Autodesk Fusion 360 part; units mm, degrees
(part 2 of 2)
equation "n_base_bolt = n_base_bolt_Ref" comment "LINKED: n_base_bolt_Ref, derived from 100000_P04_POD-SKELETON_CAD v4 (skeleton is the single source)"
equation "tube_w = 20 mm" comment "CONFIRMED: D-34, D-54: aluminium tube 20 x 40 x 1.2; the 20 mm face carries the skin, so the 40 mm runs through the wall (outer_t = ACP 3 + frame 40). The joint register may turn it for the bond width (HOLD)"
equation "tube_d = outer_t - skin_t - bond_t" comment "CALCULATION: frame depth = outer panel 46 - skin 3 - bond 3 = 40 (D-34)"
equation "tube_t = 1.2 mm" comment "CONFIRMED: D-34, D-54, D-85: perimeter members (rails, front and back stiles) keep the 1.2 mm wall; they carry the rivnuts (grip check passed)"
equation "stud_t = 1.0 mm" comment "CONFIRMED: D-85 (weight): intermediate studs at a 1.0 mm wall; they carry no rivnut, only the skin's bond line"
equation "stile_pitch_max = 400 mm" comment "CONFIRMED: D-16, D-34: members 400 mm apart or less, to keep the ACP flat"
equation "skin_setback = 0 mm" comment "ASSUMPTION: skin edge set back from the frame's top and bottom edges: 0, so the outside reveal equals the 2.26 seam gap (D-23: crisp, aligned reveals; joints register 2.8 leaves the setback to the WALL drawing)"
equation "fill_t = tube_d" comment "CALCULATION: 40 mm PET fill fills the frame depth (D-34; layout study 40 mm)"
equation "bolt_d = 7 mm" comment "CONFIRMED: PM ruling on F-009: bolt holes 7.0 (0.51 float), position tolerance 0.4 (+-0.2) from the spigot hole, CNC or drill jig (joints register FR-02)"
equation "access_d = 19 mm" comment "CALCULATION: register FR-03: passes the 18 mm head washer (ISO 7093-1, R-J10), the M6 head and the 5 mm key; holds the grommet retainer (H-02)"
equation "bolt_line_y = pod_d / 2 - skin_t - bond_t - tube_d / 2" comment "CONFIRMED: J-WALL-02 bolt line on the back panel's tube centre, Y 824 (joints register R-J15, FR-07)"
equation "rivnut_d = 9.53 mm" comment "SOURCE: Sherex CAH3-610-4.2 hole 9.53 +0.10 (HW-SEL A5; register H-03)"
equation "spigot_d = 8.5 mm" comment "ASSUMPTION: register FR-05: hole for the 8 mm locating spigot H-05"
equation "spigot_slot = 14 mm" comment "ASSUMPTION: register FR-05: slot length for the second spigot"
equation "spigot_edge = spigot_inset" comment "CALCULATION: the skeleton's spigot_inset: spigots 100 from each end of the edge (PM ruling 2026-10-31, R-J13)"
equation "bolt_edge = bolt_edge_inset" comment "CALCULATION: the skeleton's bolt_edge_inset: end bolts 220 in from the panel's ends, evenly spaced, every bolt 30 or more from any stile (PM ruling 2026-10-31, R-J14)"
equation "pocket_w = 60 mm" comment "ASSUMPTION: register FR-10: fill left out 60 x 60 next to each bolt for the key"
equation "felt_t = 9 mm" comment "SOURCE: plan VT03-PET 9 mm PET felt; HW-SEL A3; D-31 (the factory's felt)"
equation "tray_t = 0.5 mm" comment "CONFIRMED: D-37: galvanised steel tray 0.5 mm"
equation "tray_h = cass_t" comment "CONFIRMED: PM ruling 2026-10-31 (WALL group, option 1): the wall cassettes use the ceiling's tray, returns the full cassette depth (34) turned in as lips that hold the felt, no ribs; settles H09 for the walls"
equation "lip_w = 12 mm" comment "CONFIRMED: PM ruling 2026-10-31 (WALL group, option 1): 12 mm lips hold the felt edge"
equation "bend_r = tray_t" comment "ASSUMPTION: inside bend radius 1 x t for 0.5 mm DX51D (the sheet metal rule's bend radius is its Thickness); the factory's tooling sets it (guideline 9)"
equation "felt_c = 1 mm" comment "ASSUMPTION: felt edge clearance inside the returns, as the ceiling cassette"
equation "gap_h = tray_h - felt_t - 2 * tray_t" comment "CALCULATION: air gap between the tray base and the felt (24): the acoustic gap (D-17) and the cable path (D-26)"
equation "clip_zone_h = 60 mm" comment "ASSUMPTION: height of each reserved clip zone (H03: no clip named)"
equation "clip_zone_dz = 100 mm" comment "ASSUMPTION: clip zone centre from the cassette's top and bottom edges (H03)"
equation "stopw_od = 20 mm" comment "SOURCE: joints register H-08: stop washer Ø10.5 x Ø20 x 1.5 (PROPOSED part)"
equation "stopw_id = 10.5 mm" comment "SOURCE: joints register H-08"
equation "stopw_t = 1.5 mm" comment "SOURCE: joints register H-08: rivnut head 0.76 + washer 1.5 = the 2.26 stop (R-J5)"
equation "rivnut_head_d = 12.96 mm" comment "SOURCE: Sherex CAH3-610-4.2 head Ø12.96 (joints register H-03, SHX)"
equation "rivnut_head_t = 0.76 mm" comment "SOURCE: Sherex CAH3-610-4.2 head 0.76 ±0.08 (H-03, SHX)"
equation "rivnut_body_d = 9.5 mm" comment "SOURCE: Sherex CAH3-610-4.2 body Ø9.50 max (H-03, SHX)"
equation "rivnut_len = 10.16 mm" comment "SOURCE: Sherex CAH3-610-4.2 installed length 10.16 max under the head (H-03, SHX); the bulge inside the tube is not modelled"
equation "m6_d = 6 mm" comment "CALCULATION: M6 threads shown at their 6 mm major diameter (no modelled thread)"
equation "spigot_pin_d = 8 mm" comment "SOURCE: joints register H-05: Ø8 stainless pin (PROPOSED, assumption sizes)"
equation "spigot_proud = 8 mm" comment "SOURCE: joints register H-05: stands 8 proud (read as: of the joint face)"
equation "spigot_thread_l = 10 mm" comment "ASSUMPTION: M6 thread into the spigot rivnut; H-05 gives no length; 10 stays inside the rivnut's 10.16"
equation "lead_in = 1 mm" comment "SOURCE: joints register 2.10 (R-J9): 1 x 45 degree lead-in on the top edge of each closing-seam face, so the panel beside it drops in past it without catching the bulb seal"
equation "pnl_len = half_pw" comment "CALCULATION: skeleton half_pw: the back panel's skin width (1200.61 on P04)"
equation "frm_len = half_fw" comment "CALCULATION: the skeleton's half_fw, 1198.99: the frame stops close_gap / 2 from X 0 and 1.62 short of its skin (R-J16)"
equation "pnl_h = back_ph" comment "CALCULATION: skeleton back row height (1118.61 on P04)"
equation "frm_h = pnl_h" comment "CALCULATION: the frame fills the row height; the seam gaps are outside it (P04)"
equation "top_h = tube_w" comment "CALCULATION: the back panels' top rails stay 20 x 40 (the ceiling's back member is the 40 x 40, R-J3)"
equation "stile_n_mid = ceil(( frm_len - tube_w ) / stile_pitch_max) - 1" comment "CALCULATION: intermediate stiles so that no stile pitch exceeds stile_pitch_max"
equation "stile_pitch = ( frm_len - tube_w ) / ( stile_n_mid + 1 )" comment "CALCULATION: equal stile pitch, centre to centre"
equation "stile_len = frm_h - 2 * tube_w" comment "CALCULATION: stiles between the full-width rails (butt joints)"
equation "n_len_bolt = n_base_bolt" comment "CALCULATION: the skeleton's n_base_bolt (4): also on the horizontal seam and the ceiling back edge (register 2.9; the skeleton's n_ceil_back_bolt 3 is an old assumption, flagged)"
equation "len_bolt_pitch = ( frm_len - 2 * bolt_edge ) / ( n_len_bolt - 1 )" comment "CALCULATION: 253.00 on P04: 220, 473.00, 725.99, 978.99 from the frame's ends (register 2.9; the skeleton's back_base_pitch uses the 1200.61 skin and gives 253.54, flagged to its owner)"
equation "n_side_jnt = 3" comment "SOURCE: 3 bolts on the back corner and on the closing seam (register 2.9)"
equation "side_jnt_pitch = ( pnl_h - 2 * bolt_edge ) / ( n_side_jnt - 1 )" comment "CALCULATION: 339.31 on P04: 220, 559.31, 898.61 up the 1118.61 edge (register 2.9)"
equation "cass_len = pod_w / 2 - stack_t - seam_gap / 2" comment "ASSUMPTION: PROPOSED (WALL): from the side lining's face to seam_gap / 2 short of X 0. Each cassette hangs on its own panel's frame and the closing seam moves (5.2 to 5.8, register 2.11), so the skeleton's touching edges at X 0 could clash; a 2.26 gap matches the skin seam above it (R-J16) and takes the H-14 edge seal"
equation "cass_h = pnl_h" comment "CALCULATION: lower: the row height; upper: up to lin_gap under the ceiling frame, floating (D-57; P04)"
equation "d677 = panel_z0"
equation "d679 = ( -close_gap / 2 ) - ( -close_gap / 2 - half_fw )"
equation "d680 = ( pod_d / 2 - skin_t - bond_t ) - ( pod_d / 2 - outer_t )"
equation "d681 = abs(-close_gap / 2 - half_fw)"
equation "d682 = abs(pod_d / 2 - outer_t)"
equation "d683 = ( ( panel_z0 ) + tube_w ) - ( panel_z0 )"
equation "d685 = ( panel_z0 ) + tube_t"
equation "d687 = ( -close_gap / 2 ) - ( -close_gap / 2 - half_fw )"
equation "d688 = ( ( pod_d / 2 - skin_t - bond_t ) - tube_t ) - ( ( pod_d / 2 - outer_t ) + tube_t )"
equation "d689 = abs(-close_gap / 2 - half_fw)"
equation "d690 = abs(( pod_d / 2 - outer_t ) + tube_t)"
equation "d691 = ( ( ( panel_z0 ) + tube_w ) - tube_t ) - ( ( panel_z0 ) + tube_t )"
equation "d693 = ( panel_z0 + back_ph ) - top_h"
equation "d695 = ( -close_gap / 2 ) - ( -close_gap / 2 - half_fw )"
equation "d696 = ( pod_d / 2 - skin_t - bond_t ) - ( pod_d / 2 - outer_t )"
equation "d697 = abs(-close_gap / 2 - half_fw)"
equation "d698 = abs(pod_d / 2 - outer_t)"
equation "d699 = ( panel_z0 + back_ph ) - ( ( panel_z0 + back_ph ) - top_h )"
equation "d701 = ( ( panel_z0 + back_ph ) - top_h ) + tube_t"
equation "d703 = ( -close_gap / 2 ) - ( -close_gap / 2 - half_fw )"
equation "d704 = ( ( pod_d / 2 - skin_t - bond_t ) - tube_t ) - ( ( pod_d / 2 - outer_t ) + tube_t )"
equation "d705 = abs(-close_gap / 2 - half_fw)"
equation "d706 = abs(( pod_d / 2 - outer_t ) + tube_t)"
equation "d707 = ( ( panel_z0 + back_ph ) - tube_t ) - ( ( ( panel_z0 + back_ph ) - top_h ) + tube_t )"
equation "d709 = ( panel_z0 ) + tube_w"
equation "d711 = ( ( -close_gap / 2 - half_fw ) + tube_w ) - ( -close_gap / 2 - half_fw )"
equation "d712 = ( pod_d / 2 - skin_t - bond_t ) - ( pod_d / 2 - outer_t )"
equation "d713 = abs(-close_gap / 2 - half_fw)"
equation "d714 = abs(pod_d / 2 - outer_t)"
equation "d715 = ( ( panel_z0 + back_ph ) - top_h ) - ( ( panel_z0 ) + tube_w )"
equation "d717 = ( panel_z0 ) + tube_w"
equation "d719 = ( ( ( -close_gap / 2 - half_fw ) + tube_w ) - tube_t ) - ( ( -close_gap / 2 - half_fw ) + tube_t )"
equation "d720 = ( ( pod_d / 2 - skin_t - bond_t ) - tube_t ) - ( ( pod_d / 2 - outer_t ) + tube_t )"
equation "d721 = abs(( -close_gap / 2 - half_fw ) + tube_t)"
equation "d722 = abs(( pod_d / 2 - outer_t ) + tube_t)"
equation "d723 = ( ( panel_z0 + back_ph ) - top_h ) - ( ( panel_z0 ) + tube_w )"
equation "d725 = ( panel_z0 ) + tube_w"
equation "d727 = ( -close_gap / 2 ) - ( ( -close_gap / 2 ) - tube_w )"
equation "d728 = ( pod_d / 2 - skin_t - bond_t ) - ( pod_d / 2 - outer_t )"
equation "d729 = abs(( -close_gap / 2 ) - tube_w)"
equation "d730 = abs(pod_d / 2 - outer_t)"
equation "d731 = ( ( panel_z0 + back_ph ) - top_h ) - ( ( panel_z0 ) + tube_w )"
equation "d733 = ( panel_z0 ) + tube_w"
equation "d735 = ( ( -close_gap / 2 ) - tube_t ) - ( ( ( -close_gap / 2 ) - tube_w ) + tube_t )"
equation "d736 = ( ( pod_d / 2 - skin_t - bond_t ) - tube_t ) - ( ( pod_d / 2 - outer_t ) + tube_t )"
equation "d737 = abs(( ( -close_gap / 2 ) - tube_w ) + tube_t)"
equation "d738 = abs(( pod_d / 2 - outer_t ) + tube_t)"
equation "d739 = ( ( panel_z0 + back_ph ) - top_h ) - ( ( panel_z0 ) + tube_w )"
equation "d741 = ( panel_z0 ) + tube_w"
equation "d743 = ( ( -close_gap / 2 - half_fw ) + stile_pitch + tube_w ) - ( ( -close_gap / 2 - half_fw ) + stile_pitch )"
equation "d744 = ( pod_d / 2 - skin_t - bond_t ) - ( pod_d / 2 - outer_t )"
equation "d745 = abs(( -close_gap / 2 - half_fw ) + stile_pitch)"
equation "d746 = abs(pod_d / 2 - outer_t)"
equation "d747 = ( ( panel_z0 + back_ph ) - top_h ) - ( ( panel_z0 ) + tube_w )"
equation "d749 = ( panel_z0 ) + tube_w"
equation "d751 = ( ( ( -close_gap / 2 - half_fw ) + stile_pitch + tube_w ) - stud_t ) - ( ( ( -close_gap / 2 - half_fw ) + stile_pitch ) + stud_t )"
equation "d752 = ( ( pod_d / 2 - skin_t - bond_t ) - stud_t ) - ( ( pod_d / 2 - outer_t ) + stud_t )"
equation "d753 = abs(( ( -close_gap / 2 - half_fw ) + stile_pitch ) + stud_t)"
equation "d754 = abs(( pod_d / 2 - outer_t ) + stud_t)"
equation "d755 = ( ( panel_z0 + back_ph ) - top_h ) - ( ( panel_z0 ) + tube_w )"
equation "d757 = stile_n_mid"
equation "d759 = stile_pitch"
equation "d761 = ( panel_z0 ) + skin_setback"
equation "d763 = ( -seam_gap / 2 ) - ( -seam_gap / 2 - half_pw )"
equation "d764 = ( pod_d / 2 ) - ( pod_d / 2 - skin_t )"
equation "d765 = abs(-seam_gap / 2 - half_pw)"
equation "d766 = abs(pod_d / 2 - skin_t)"
equation "d767 = ( ( panel_z0 + back_ph ) - skin_setback ) - ( ( panel_z0 ) + skin_setback )"
equation "d769 = ( panel_z0 ) + tube_w"
equation "d771 = ( ( -close_gap / 2 - half_fw ) + stile_pitch ) - ( ( -close_gap / 2 - half_fw ) + tube_w )"
equation "d772 = ( pod_d / 2 - skin_t - bond_t ) - ( pod_d / 2 - outer_t )"
equation "d773 = abs(( -close_gap / 2 - half_fw ) + tube_w)"
equation "d774 = abs(pod_d / 2 - outer_t)"
equation "d775 = ( ( panel_z0 + back_ph ) - top_h ) - ( ( panel_z0 ) + tube_w )"
equation "d777 = stile_n_mid + 1"
equation "d779 = stile_pitch"
equation "d781 = ( panel_z0 ) + tube_w"
equation "d783 = ( ( ( -close_gap / 2 - half_fw ) + bolt_edge + 0 * len_bolt_pitch ) + pocket_w / 2 ) - ( ( ( -close_gap / 2 - half_fw ) + bolt_edge + 0 * len_bolt_pitch ) - pocket_w / 2 )"
equation "d784 = ( pod_d / 2 - skin_t - bond_t ) - ( pod_d / 2 - outer_t )"
equation "d785 = abs(( ( -close_gap / 2 - half_fw ) + bolt_edge + 0 * len_bolt_pitch ) - pocket_w / 2)"
equation "d786 = abs(pod_d / 2 - outer_t)"
equation "d787 = ( ( ( panel_z0 ) + tube_w ) + pocket_w ) - ( ( panel_z0 ) + tube_w )"
equation "d789 = ( panel_z0 ) + tube_w"
equation "d791 = ( ( ( -close_gap / 2 - half_fw ) + bolt_edge + 1 * len_bolt_pitch ) + pocket_w / 2 ) - ( ( ( -close_gap / 2 - half_fw ) + bolt_edge + 1 * len_bolt_pitch ) - pocket_w / 2 )"
equation "d792 = ( pod_d / 2 - skin_t - bond_t ) - ( pod_d / 2 - outer_t )"
equation "d793 = abs(( ( -close_gap / 2 - half_fw ) + bolt_edge + 1 * len_bolt_pitch ) - pocket_w / 2)"
equation "d794 = abs(pod_d / 2 - outer_t)"
equation "d795 = ( ( ( panel_z0 ) + tube_w ) + pocket_w ) - ( ( panel_z0 ) + tube_w )"
equation "d797 = ( panel_z0 ) + tube_w"
equation "d799 = ( ( ( -close_gap / 2 - half_fw ) + bolt_edge + 2 * len_bolt_pitch ) + pocket_w / 2 ) - ( ( ( -close_gap / 2 - half_fw ) + bolt_edge + 2 * len_bolt_pitch ) - pocket_w / 2 )"
equation "d800 = ( pod_d / 2 - skin_t - bond_t ) - ( pod_d / 2 - outer_t )"
equation "d801 = abs(( ( -close_gap / 2 - half_fw ) + bolt_edge + 2 * len_bolt_pitch ) - pocket_w / 2)"
equation "d802 = abs(pod_d / 2 - outer_t)"
equation "d803 = ( ( ( panel_z0 ) + tube_w ) + pocket_w ) - ( ( panel_z0 ) + tube_w )"
equation "d805 = ( panel_z0 ) + tube_w"
equation "d807 = ( ( ( -close_gap / 2 - half_fw ) + bolt_edge + 3 * len_bolt_pitch ) + pocket_w / 2 ) - ( ( ( -close_gap / 2 - half_fw ) + bolt_edge + 3 * len_bolt_pitch ) - pocket_w / 2 )"
equation "d808 = ( pod_d / 2 - skin_t - bond_t ) - ( pod_d / 2 - outer_t )"
equation "d809 = abs(( ( -close_gap / 2 - half_fw ) + bolt_edge + 3 * len_bolt_pitch ) - pocket_w / 2)"
equation "d810 = abs(pod_d / 2 - outer_t)"
equation "d811 = ( ( ( panel_z0 ) + tube_w ) + pocket_w ) - ( ( panel_z0 ) + tube_w )"
equation "d813 = ( ( panel_z0 ) + bolt_edge + 0 * side_jnt_pitch ) - pocket_w / 2"
equation "d815 = ( ( ( -close_gap / 2 - half_fw ) + 1 * tube_w ) + pocket_w ) - ( ( -close_gap / 2 - half_fw ) + 1 * tube_w )"
equation "d816 = ( pod_d / 2 - skin_t - bond_t ) - ( pod_d / 2 - outer_t )"
equation "d817 = abs(( -close_gap / 2 - half_fw ) + 1 * tube_w)"
equation "d818 = abs(pod_d / 2 - outer_t)"
equation "d819 = ( ( ( panel_z0 ) + bolt_edge + 0 * side_jnt_pitch ) + pocket_w / 2 ) - ( ( ( panel_z0 ) + bolt_edge + 0 * side_jnt_pitch ) - pocket_w / 2 )"
equation "d821 = ( ( panel_z0 ) + bolt_edge + 1 * side_jnt_pitch ) - pocket_w / 2"
equation "d823 = ( ( ( -close_gap / 2 - half_fw ) + 1 * tube_w ) + pocket_w ) - ( ( -close_gap / 2 - half_fw ) + 1 * tube_w )"
equation "d824 = ( pod_d / 2 - skin_t - bond_t ) - ( pod_d / 2 - outer_t )"
equation "d825 = abs(( -close_gap / 2 - half_fw ) + 1 * tube_w)"
equation "d826 = abs(pod_d / 2 - outer_t)"
equation "d827 = ( ( ( panel_z0 ) + bolt_edge + 1 * side_jnt_pitch ) + pocket_w / 2 ) - ( ( ( panel_z0 ) + bolt_edge + 1 * side_jnt_pitch ) - pocket_w / 2 )"
equation "d829 = ( ( panel_z0 ) + bolt_edge + 2 * side_jnt_pitch ) - pocket_w / 2"
equation "d831 = ( ( ( -close_gap / 2 - half_fw ) + 1 * tube_w ) + pocket_w ) - ( ( -close_gap / 2 - half_fw ) + 1 * tube_w )"
equation "d832 = ( pod_d / 2 - skin_t - bond_t ) - ( pod_d / 2 - outer_t )"
equation "d833 = abs(( -close_gap / 2 - half_fw ) + 1 * tube_w)"
equation "d834 = abs(pod_d / 2 - outer_t)"
equation "d835 = ( ( ( panel_z0 ) + bolt_edge + 2 * side_jnt_pitch ) + pocket_w / 2 ) - ( ( ( panel_z0 ) + bolt_edge + 2 * side_jnt_pitch ) - pocket_w / 2 )"
equation "d837 = panel_z0"
equation "d839 = abs(( -close_gap / 2 - half_fw ) + bolt_edge)"
equation "d840 = abs(pod_d / 2 - skin_t - bond_t - tube_d / 2)"
equation "d841 = tube_t"
equation "d842 = bolt_d"
equation "d844 = ( panel_z0 ) + tube_w"
equation "d846 = abs(( -close_gap / 2 - half_fw ) + bolt_edge)"
equation "d847 = abs(pod_d / 2 - skin_t - bond_t - tube_d / 2)"
equation "d848 = tube_t"
equation "d849 = access_d"
equation "d851 = n_len_bolt"
equation "d853 = len_bolt_pitch"
equation "d855 = panel_z0"
equation "d857 = abs(( -close_gap / 2 ) - 1 * spigot_edge)"
equation "d858 = abs(pod_d / 2 - skin_t - bond_t - tube_d / 2)"
equation "d859 = tube_t"
equation "d860 = spigot_d"
equation "d862 = panel_z0"
equation "d864 = ( ( ( -close_gap / 2 - half_fw ) + 1 * spigot_edge ) + ( spigot_slot - spigot_d ) / 2 ) - ( ( ( -close_gap / 2 - half_fw ) + 1 * spigot_edge ) - ( spigot_slot - spigot_d ) / 2 )"
equation "d865 = ( ( pod_d / 2 - skin_t - bond_t - tube_d / 2 ) + spigot_d / 2 ) - ( ( pod_d / 2 - skin_t - bond_t - tube_d / 2 ) - spigot_d / 2 )"
equation "d866 = abs(( ( -close_gap / 2 - half_fw ) + 1 * spigot_edge ) - ( spigot_slot - spigot_d ) / 2)"
equation "d867 = abs(( pod_d / 2 - skin_t - bond_t - tube_d / 2 ) - spigot_d / 2)"
equation "d868 = ( ( panel_z0 ) + tube_t ) - ( panel_z0 )"
equation "d870 = panel_z0"
equation "d872 = abs(( ( -close_gap / 2 - half_fw ) + 1 * spigot_edge ) - ( spigot_slot - spigot_d ) / 2)"
equation "d873 = abs(pod_d / 2 - skin_t - bond_t - tube_d / 2)"
equation "d874 = tube_t"
equation "d875 = spigot_d"
equation "d877 = panel_z0"
equation "d879 = abs(( ( -close_gap / 2 - half_fw ) + 1 * spigot_edge ) + ( spigot_slot - spigot_d ) / 2)"
equation "d880 = abs(pod_d / 2 - skin_t - bond_t - tube_d / 2)"
equation "d881 = tube_t"
equation "d882 = spigot_d"
equation "d884 = panel_z0 + back_ph"
equation "d886 = abs(( -close_gap / 2 - half_fw ) + bolt_edge)"
equation "d887 = abs(pod_d / 2 - skin_t - bond_t - tube_d / 2)"
equation "d888 = tube_t"
equation "d889 = rivnut_d"
equation "d891 = n_len_bolt"
equation "d893 = len_bolt_pitch"
equation "d895 = panel_z0 + back_ph"
equation "d897 = abs(( -close_gap / 2 - half_fw ) + spigot_edge)"
equation "d898 = abs(pod_d / 2 - skin_t - bond_t - tube_d / 2)"
equation "d899 = tube_t"
equation "d900 = rivnut_d"
equation "d902 = panel_z0 + back_ph"
equation "d904 = abs(( -close_gap / 2 ) - spigot_edge)"
equation "d905 = abs(pod_d / 2 - skin_t - bond_t - tube_d / 2)"
equation "d906 = tube_t"
equation "d907 = rivnut_d"
equation "d909 = -close_gap / 2 - half_fw"
equation "d911 = abs(bolt_line_y)"
equation "d912 = abs(( panel_z0 ) + bolt_edge)"
equation "d913 = tube_t"
equation "d914 = bolt_d"
equation "d916 = ( -close_gap / 2 - half_fw ) + 1 * tube_w"
equation "d918 = abs(bolt_line_y)"
equation "d919 = abs(( panel_z0 ) + bolt_edge)"
equation "d920 = tube_t"
equation "d921 = access_d"
equation "d923 = n_side_jnt"
equation "d925 = side_jnt_pitch"
equation "d927 = -close_gap / 2"
equation "d929 = abs(pod_d / 2 - skin_t - bond_t - tube_d / 2)"
equation "d930 = abs(( panel_z0 ) + bolt_edge)"
equation "d931 = tube_t"
equation "d932 = bolt_d"
equation "d934 = n_side_jnt"
equation "d936 = side_jnt_pitch"
equation "d938 = lead_in"
equation "d939 = panel_z0 + back_ph"
equation "d941 = abs(( -close_gap / 2 - half_fw ) + bolt_edge)"
equation "d942 = abs(pod_d / 2 - skin_t - bond_t - tube_d / 2)"
equation "d943 = stopw_od"
equation "d944 = stopw_id"
equation "d945 = stopw_t"
equation "d947 = ( panel_z0 + back_ph ) + stopw_t"
equation "d949 = abs(( -close_gap / 2 - half_fw ) + bolt_edge)"
equation "d950 = abs(pod_d / 2 - skin_t - bond_t - tube_d / 2)"
equation "d951 = rivnut_head_d"
equation "d952 = m6_d"
equation "d953 = rivnut_head_t"
equation "d955 = ( panel_z0 + back_ph ) + stopw_t"
equation "d957 = abs(( -close_gap / 2 - half_fw ) + bolt_edge)"
equation "d958 = abs(pod_d / 2 - skin_t - bond_t - tube_d / 2)"
equation "d959 = rivnut_body_d"
equation "d960 = m6_d"
equation "d963 = -( rivnut_len )"
equation "d965 = n_len_bolt"
equation "d967 = len_bolt_pitch"
equation "d969 = n_len_bolt"
equation "d971 = len_bolt_pitch"
equation "d973 = panel_z0 + back_ph"
equation "d975 = abs(( -close_gap / 2 - half_fw ) + spigot_edge)"
equation "d976 = abs(pod_d / 2 - skin_t - bond_t - tube_d / 2)"
equation "d977 = rivnut_head_d"
equation "d978 = m6_d"
equation "d979 = rivnut_head_t"
equation "d981 = panel_z0 + back_ph"
equation "d983 = abs(( -close_gap / 2 - half_fw ) + spigot_edge)"
equation "d984 = abs(pod_d / 2 - skin_t - bond_t - tube_d / 2)"
equation "d985 = rivnut_body_d"
equation "d986 = m6_d"
equation "d989 = -( rivnut_len )"
equation "d991 = ( panel_z0 + back_ph ) + rivnut_head_t"
equation "d993 = abs(( -close_gap / 2 - half_fw ) + spigot_edge)"
equation "d994 = abs(pod_d / 2 - skin_t - bond_t - tube_d / 2)"
equation "d995 = spigot_pin_d"
equation "d996 = spigot_proud - rivnut_head_t"
equation "d998 = ( panel_z0 + back_ph ) + rivnut_head_t"
equation "d1000 = abs(( -close_gap / 2 - half_fw ) + spigot_edge)"
equation "d1001 = abs(pod_d / 2 - skin_t - bond_t - tube_d / 2)"
equation "d1002 = m6_d"
equation "d1005 = -( spigot_thread_l )"
equation "d1007 = panel_z0 + back_ph"
equation "d1009 = abs(( -close_gap / 2 ) - spigot_edge)"
equation "d1010 = abs(pod_d / 2 - skin_t - bond_t - tube_d / 2)"
equation "d1011 = rivnut_head_d"
equation "d1012 = m6_d"
equation "d1013 = rivnut_head_t"
equation "d1015 = panel_z0 + back_ph"
equation "d1017 = abs(( -close_gap / 2 ) - spigot_edge)"
equation "d1018 = abs(pod_d / 2 - skin_t - bond_t - tube_d / 2)"
equation "d1019 = rivnut_body_d"
equation "d1020 = m6_d"
equation "d1023 = -( rivnut_len )"
equation "d1025 = ( panel_z0 + back_ph ) + rivnut_head_t"
equation "d1027 = abs(( -close_gap / 2 ) - spigot_edge)"
equation "d1028 = abs(pod_d / 2 - skin_t - bond_t - tube_d / 2)"
equation "d1029 = spigot_pin_d"
equation "d1030 = spigot_proud - rivnut_head_t"
equation "d1032 = ( panel_z0 + back_ph ) + rivnut_head_t"
equation "d1034 = abs(( -close_gap / 2 ) - spigot_edge)"
equation "d1035 = abs(pod_d / 2 - skin_t - bond_t - tube_d / 2)"
equation "d1036 = m6_d"
equation "d1039 = -( spigot_thread_l )"
named bodies: "RAIL - BOTTOM", "RAIL - TOP", "STILE - OUTER", "STILE - CENTRE", "STILE - MID 1", "STILE - MID 2", "SKIN - ACP 3, OVERHANGS THE FRAME 1.62 AT THE CLOSING SEAM", "FILL - BAY 1", "FILL - BAY 2", "FILL - BAY 3", "STOP WASHER - TOP RAIL 1", "RIVNUT - TOP RAIL 1", "STOP WASHER - TOP RAIL 2", "STOP WASHER - TOP RAIL 3", "STOP WASHER - TOP RAIL 4", "RIVNUT - TOP RAIL 2", "RIVNUT - TOP RAIL 3", "RIVNUT - TOP RAIL 4", "RIVNUT - TOP RAIL SPIGOT LOW X", "SPIGOT - TOP RAIL SPIGOT LOW X", "RIVNUT - TOP RAIL SPIGOT HIGH X", "SPIGOT - TOP RAIL SPIGOT HIGH X"
